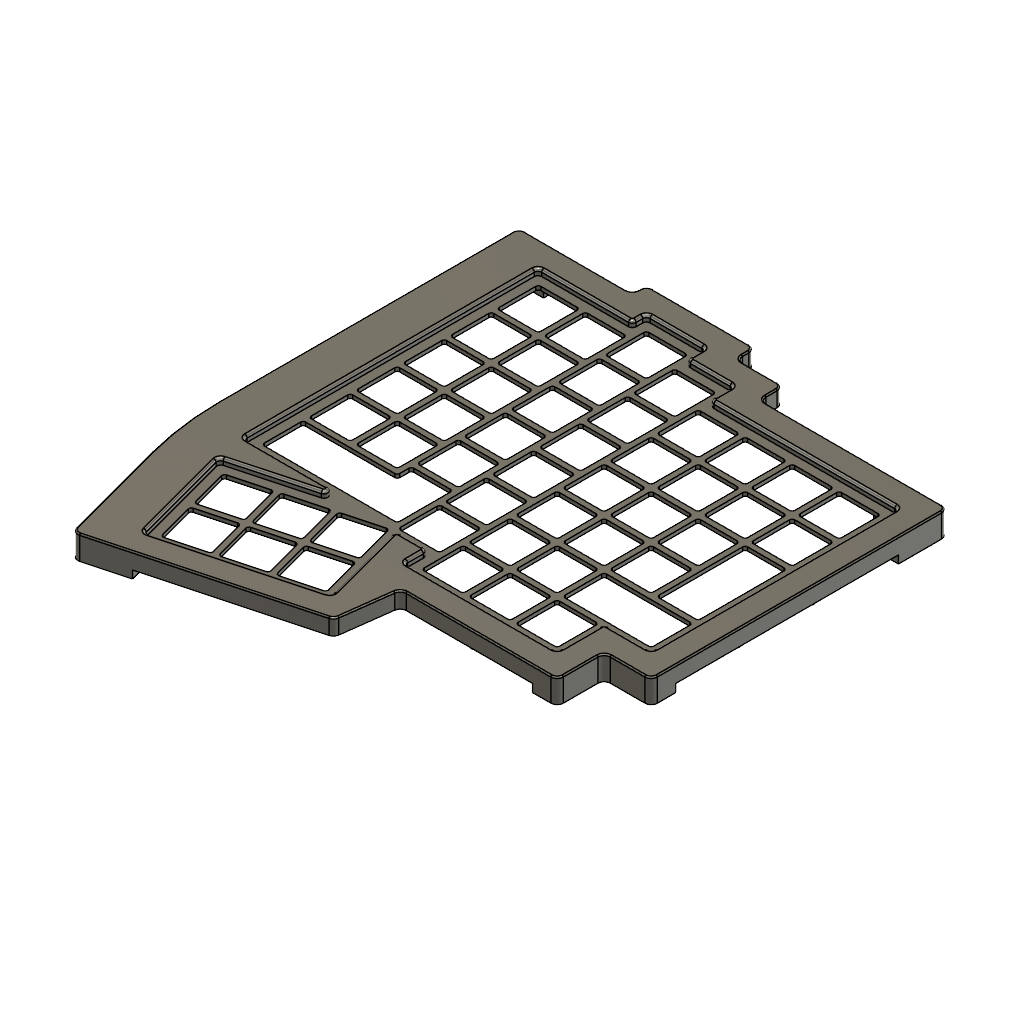
Assembly (Pollux) (Autodesk Fusion 360 archive; units mm, degrees)
design "Case Top (Pollux)" references "_Base (Pollux)"
part number: 2026-10-18-20-24-08-902
Autodesk Fusion 360 part; units mm, degrees
(part 1 of 6)
derive "ExternalDerived1"
sketch "Sketch2" plane through (0, 0, 0) normal (0, 1, 0) x (1, 0, 0)
  line L0 (-76.2, 57.15) -> (-76.2, -57.15) construction
  line L1 (76.2, -49.53) -> (76.2, 45.72) construction
  line L2 (-76.2, 57.15) -> (-38.1, 57.15) construction
  line L3 (-38.1, 57.15) -> (-38.1, 62.865) construction
  line L4 (-38.1, 62.865) -> (-19.05, 62.865) construction
  line L5 (-19.05, 62.865) -> (-19.05, 55.245) construction
  line L6 (-19.05, 55.245) -> (0, 55.245) construction
  line L7 (0, 55.245) -> (0, 45.72) construction
  line L8 (0, 45.72) -> (76.2, 45.72) construction
  line L9 (0, 45.72) -> (19.05, 45.72) construction
  line L10 (38.1, 45.72) -> (57.15, 45.72) construction
  line L11 (-76.2, 57.15) -> (-57.15, 57.15) construction
  line L12 (-57.15, 57.15) -> (-57.15, 38.1) construction
  line L13 (-57.15, 38.1) -> (-76.2, 38.1) construction
  line L14 (-38.1, 57.15) -> (-38.1, -38.1) construction
  line L15 (-38.1, -38.1) -> (-76.2, -38.1) construction
  line L16 (-57.15, 38.1) -> (-76.2, 57.15) construction
  line L17 (-76.2, 38.1) -> (-57.15, 57.15) construction
  line L18 (-19.05, 55.245) -> (-19.05, 43.815) construction
  line L19 (-19.05, 43.815) -> (-38.1, 43.815) construction
  line L20 (-19.05, 43.815) -> (-19.05, -32.385) construction
  line L21 (-19.05, -32.385) -> (-38.1, -32.385) construction
  line L22 (-38.1, 62.865) -> (-19.05, 43.815) construction
  line L23 (-38.1, 43.815) -> (-19.05, 62.865) construction
  line L24 (0, 45.72) -> (0, 36.195) construction
  line L25 (0, 36.195) -> (-19.05, 36.195) construction
  line L26 (0, 36.195) -> (0, -59.055) construction
  line L27 (0, -59.055) -> (-19.05, -59.055) construction
  line L28 (-19.05, -59.055) -> (-19.05, -32.385) construction
  line L29 (19.05, 45.72) -> (19.05, 26.67) construction
  line L30 (19.05, 26.67) -> (0, 26.67) construction
  line L31 (19.05, 26.67) -> (0, 45.72) construction
  line L32 (19.05, 45.72) -> (0, 26.67) construction
  line L33 (38.1, 45.72) -> (38.1, -68.58) construction
  line L34 (38.1, -68.58) -> (0, -68.58) construction
  line L35 (0, -68.58) -> (0, -59.055) construction
  line L36 (38.1, -68.58) -> (57.15, -68.58) construction
  line L37 (57.15, -68.58) -> (57.15, -49.53) construction
  line L38 (57.15, -49.53) -> (38.1, -49.53) construction
  line L39 (57.15, -49.53) -> (76.2, -49.53) construction
  line L40 (-76.2, -57.15) -> (-19.05, -57.15) construction
  line L41 (57.15, 45.72) -> (57.15, 26.67) construction
  line L42 (57.15, 26.67) -> (38.1, 26.67) construction
  line L43 (57.15, 26.67) -> (38.1, 45.72) construction
  line L44 (38.1, 26.67) -> (57.15, 45.72) construction
  line L45 (38.1, 26.67) -> (38.1, 7.62) construction
  line L46 (38.1, 7.62) -> (76.2, 7.62) construction
  line L47 (57.15, 7.62) -> (57.15, -30.48) construction
  line L48 (57.15, -30.48) -> (38.1, -30.48) construction
  line L49 (57.15, -11.43) -> (38.1, -11.43) construction
  line L50 (57.15, -30.48) -> (76.2, -30.48) construction
  line L51 (57.15, 7.62) -> (76.2, -30.48) construction
  line L52 (57.15, -30.48) -> (76.2, 7.62) construction
  line L53 (38.1, 7.62) -> (57.15, -11.43) construction
  line L54 (57.15, 7.62) -> (38.1, -11.43) construction
  line L55 (38.1, -30.48) -> (76.2, -49.53) construction
  line L56 (76.2, -30.48) -> (38.1, -49.53) construction
  line L57 (38.1, -49.53) -> (57.15, -68.58) construction
  line L58 (57.15, -49.53) -> (38.1, -68.58) construction
  line L59 (-76.2, -38.1) -> (-19.05, -57.15) construction
  line L60 (-38.1, -38.1) -> (-19.05, -38.1) construction
  line L61 (-19.05, -38.1) -> (-76.2, -57.15) construction
  line L62 (-76.2, 57.15) -> (-86.56, 57.15) construction
  line L63 (-86.56, 57.15) -> (-86.56, 59.625) construction
  line L64 (-38.1, 57.15) -> (-40.575, 57.15) construction
  line L65 (-40.575, 57.15) -> (-40.575, 59.625) construction
  line L66 (-38.1, 62.865) -> (-38.1, 65.34) construction
  line L67 (-38.1, 65.34) -> (-40.575, 65.34) construction
  line L68 (-19.05, 62.865) -> (-19.05, 65.34) construction
  line L69 (-19.05, 65.34) -> (-16.575, 65.34) construction
  line L70 (-19.05, 55.245) -> (-16.575, 55.245) construction
  line L71 (-16.575, 55.245) -> (-16.575, 57.72) construction
  line L72 (0, 55.245) -> (2.475, 55.245) construction
  line L73 (2.475, 55.245) -> (2.475, 57.72) construction
  line L74 (0, 45.72) -> (2.475, 45.72) construction
  line L75 (2.475, 45.72) -> (2.475, 48.195) construction
  line L76 (76.2, 45.72) -> (78.675, 45.72) construction
  line L77 (78.675, 45.72) -> (78.675, 48.195) construction
  line L78 (76.2, -49.53) -> (78.675, -49.53) construction
  line L79 (78.675, -49.53) -> (78.675, -52.005) construction
  line L80 (57.15, -49.53) -> (59.625, -49.53) construction
  line L81 (59.625, -49.53) -> (59.625, -52.005) construction
  line L82 (57.15, -68.58) -> (59.625, -68.58) construction
  line L83 (59.625, -68.58) -> (59.625, -71.055) construction
  line L84 (-19.05, -59.055) -> (-19.05, -59.16) construction
  line L85 (-19.05, -59.16) -> (-19.115, -59.16) construction
  line L86 (-19.115, -59.16) -> (-19.2509, -58.6529) construction
  line L87 (-19.2509, -58.6529) -> (-18.7438, -58.517) construction
  line L88 (-18.7438, -58.517) -> (-37.1447, -63.4475) construction
  line L89 (-37.1447, -63.4475) -> (-32.2142, -81.8484) construction
  line L90 (-32.2142, -81.8484) -> (-13.8133, -76.9179) construction
  line L91 (-13.8133, -76.9179) -> (-18.7438, -58.517) construction
  line L92 (-37.1447, -63.4475) -> (-73.9464, -73.3085) construction
  line L93 (-73.9464, -73.3085) -> (-64.0854, -110.1103) construction
  line L94 (-64.0854, -110.1103) -> (-8.8828, -95.3188) construction
  line L95 (-8.8828, -95.3188) -> (-13.8133, -76.9179) construction
  line L96 (-37.1447, -63.4475) -> (-13.8133, -76.9179) construction
  line L97 (-32.2142, -81.8484) -> (-18.7438, -58.517) construction
  line L98 (0, -68.58) -> (-2.475, -68.58) construction
  line L99 (-2.475, -68.58) -> (-2.475, -71.055) construction
  line L100 (-8.8828, -95.3188) -> (-6.4921, -94.6782) construction
  line L101 (-6.4921, -94.6782) -> (-5.8515, -97.0689) construction
  line L102 (-64.0854, -110.1103) -> (-74.0924, -112.7917) construction
  line L103 (-74.0924, -112.7917) -> (-73.4518, -115.1823) construction
  line L104 (-73.9464, -73.3085) -> (-83.9534, -75.9899) construction
  line L105 (-83.9534, -75.9899) -> (-84.594, -73.5992) construction
  line L106 (-76.2, -57.15) -> (-76.2, -59.625) construction
  line L107 (-76.2, -59.625) -> (-86.56, -59.625) construction
  line L108 (-84.594, -73.5992) -> (-73.4518, -115.1823)
  line L109 (-73.4518, -115.1823) -> (-5.8515, -97.0689)
  line L110 (-5.8515, -97.0689) -> (-2.475, -71.055)
  line L111 (-2.475, -71.055) -> (59.625, -71.055)
  line L112 (59.625, -71.055) -> (59.625, -52.005)
  line L113 (59.625, -52.005) -> (78.675, -52.005)
  line L114 (78.675, -52.005) -> (78.675, 48.195)
  line L115 (78.675, 48.195) -> (2.475, 48.195)
  line L116 (2.475, 48.195) -> (2.475, 57.72)
  line L117 (2.475, 57.72) -> (-16.575, 57.72)
  line L118 (-16.575, 57.72) -> (-16.575, 65.34)
  line L119 (-16.575, 65.34) -> (-40.575, 65.34)
  line L120 (-40.575, 65.34) -> (-40.575, 59.625)
  line L121 (-40.575, 59.625) -> (-86.56, 59.625)
  line L122 (-86.56, 59.625) -> (-86.56, -59.625)
  line L123 (-86.56, -59.625) -> (-84.594, -73.5992)
  line L124 (-19.5569, -59.9255) -> (-35.7362, -64.2607)
  line L125 (-35.7362, -64.2607) -> (-31.401, -80.4399)
  line L126 (-31.401, -80.4399) -> (-15.2217, -76.1047)
  line L127 (-15.2217, -76.1047) -> (-19.5569, -59.9255)
  line L128 (-19.5569, -59.9255) -> (-31.401, -80.4399) construction
  line L129 (-35.7362, -64.2607) -> (-15.2217, -76.1047) construction
  line L130 (-58.3, 56) -> (-75.05, 56)
  line L131 (-75.05, 56) -> (-75.05, 39.25)
  line L132 (-75.05, 39.25) -> (-58.3, 39.25)
  line L133 (-58.3, 39.25) -> (-58.3, 56)
  line L134 (-58.3, 56) -> (-75.05, 39.25) construction
  line L135 (-75.05, 56) -> (-58.3, 39.25) construction
  line L136 (-20.2, 61.715) -> (-36.95, 61.715)
  line L137 (-36.95, 61.715) -> (-36.95, 44.965)
  line L138 (-36.95, 44.965) -> (-20.2, 44.965)
  line L139 (-20.2, 44.965) -> (-20.2, 61.715)
  line L140 (-20.2, 61.715) -> (-36.95, 44.965) construction
  line L141 (-36.95, 61.715) -> (-20.2, 44.965) construction
  line L142 (-19.05, 55.245) -> (0, 36.195) construction
  line L143 (-19.05, 36.195) -> (0, 55.245) construction
  line L144 (-1.15, 54.095) -> (-17.9, 54.095)
  line L145 (-17.9, 54.095) -> (-17.9, 37.345)
  line L146 (-17.9, 37.345) -> (-1.15, 37.345)
  line L147 (-1.15, 37.345) -> (-1.15, 54.095)
  line L148 (-1.15, 54.095) -> (-17.9, 37.345) construction
  line L149 (-17.9, 54.095) -> (-1.15, 37.345) construction
  line L150 (17.9, 44.57) -> (1.15, 44.57)
  line L151 (1.15, 44.57) -> (1.15, 27.82)
  line L152 (1.15, 27.82) -> (17.9, 27.82)
  line L153 (17.9, 27.82) -> (17.9, 44.57)
  line L154 (17.9, 44.57) -> (1.15, 27.82) construction
  line L155 (1.15, 44.57) -> (17.9, 27.82) construction
  line L156 (56, 44.57) -> (39.25, 44.57)
  line L157 (39.25, 44.57) -> (39.25, 27.82)
  line L158 (39.25, 27.82) -> (56, 27.82)
  line L159 (56, 27.82) -> (56, 44.57)
  line L160 (56, 44.57) -> (39.25, 27.82) construction
  line L161 (39.25, 44.57) -> (56, 27.82) construction
  line L162 (56, 6.47) -> (39.25, 6.47)
  line L163 (39.25, 6.47) -> (39.25, -10.28)
  line L164 (39.25, -10.28) -> (56, -10.28)
  line L165 (56, -10.28) -> (56, 6.47)
  line L166 (56, 6.47) -> (39.25, -10.28) construction
  line L167 (39.25, 6.47) -> (56, -10.28) construction
  line L168 (75.05, 6.47) -> (58.3, 6.47)
  line L169 (58.3, 6.47) -> (58.3, -29.33)
  line L170 (58.3, -29.33) -> (75.05, -29.33)
  line L171 (75.05, -29.33) -> (75.05, 6.47)
  line L172 (75.05, 6.47) -> (58.3, -29.33) construction
  line L173 (58.3, 6.47) -> (75.05, -29.33) construction
  line L174 (75.05, -31.63) -> (39.25, -31.63)
  line L175 (39.25, -31.63) -> (39.25, -48.38)
  line L176 (39.25, -48.38) -> (75.05, -48.38)
  line L177 (75.05, -48.38) -> (75.05, -31.63)
  line L178 (75.05, -31.63) -> (39.25, -48.38) construction
  line L179 (39.25, -31.63) -> (75.05, -48.38) construction
  line L180 (56, -50.68) -> (39.25, -50.68)
  line L181 (39.25, -50.68) -> (39.25, -67.43)
  line L182 (39.25, -67.43) -> (56, -67.43)
  line L183 (56, -67.43) -> (56, -50.68)
  line L184 (56, -50.68) -> (39.25, -67.43) construction
  line L185 (39.25, -50.68) -> (56, -67.43) construction
  line L186 (-56, 56) -> (-56, 39.25)
  line L187 (-56, 39.25) -> (-39.25, 39.25)
  line L188 (-39.25, 39.25) -> (-39.25, 56)
  line L189 (-39.25, 56) -> (-56, 56)
  line L190 (-75.05, 36.95) -> (-75.05, 20.2)
  line L191 (-75.05, 20.2) -> (-58.3, 20.2)
  line L192 (-58.3, 20.2) -> (-58.3, 36.95)
  line L193 (-58.3, 36.95) -> (-75.05, 36.95)
  line L194 (-56, 36.95) -> (-56, 20.2)
  line L195 (-56, 20.2) -> (-39.25, 20.2)
  line L196 (-39.25, 20.2) -> (-39.25, 36.95)
  line L197 (-39.25, 36.95) -> (-56, 36.95)
  line L198 (-75.05, 17.9) -> (-75.05, 1.15)
  line L199 (-75.05, 1.15) -> (-58.3, 1.15)
  line L200 (-58.3, 1.15) -> (-58.3, 17.9)
  line L201 (-58.3, 17.9) -> (-75.05, 17.9)
  line L202 (-56, 17.9) -> (-56, 1.15)
  line L203 (-56, 1.15) -> (-39.25, 1.15)
  line L204 (-39.25, 1.15) -> (-39.25, 17.9)
  line L205 (-39.25, 17.9) -> (-56, 17.9)
  line L206 (-75.05, -1.15) -> (-75.05, -17.9)
  line L207 (-75.05, -17.9) -> (-58.3, -17.9)
  line L208 (-58.3, -17.9) -> (-58.3, -1.15)
  line L209 (-58.3, -1.15) -> (-75.05, -1.15)
  line L210 (-56, -1.15) -> (-56, -17.9)
  line L211 (-56, -17.9) -> (-39.25, -17.9)
  line L212 (-39.25, -17.9) -> (-39.25, -1.15)
  line L213 (-39.25, -1.15) -> (-56, -1.15)
  line L214 (-75.05, -20.2) -> (-75.05, -36.95)
  line L215 (-75.05, -36.95) -> (-58.3, -36.95)
  line L216 (-58.3, -36.95) -> (-58.3, -20.2)
  line L217 (-58.3, -20.2) -> (-75.05, -20.2)
  line L218 (-56, -20.2) -> (-56, -36.95)
  line L219 (-56, -36.95) -> (-39.25, -36.95)
  line L220 (-39.25, -36.95) -> (-39.25, -20.2)
  line L221 (-39.25, -20.2) -> (-56, -20.2)
  line L222 (-20.2, -39.25) -> (-75.05, -39.25)
  line L223 (-75.05, -39.25) -> (-75.05, -56)
  line L224 (-75.05, -56) -> (-20.2, -56)
  line L225 (-20.2, -56) -> (-20.2, -39.25)
  line L226 (-20.2, -39.25) -> (-75.05, -56) construction
  line L227 (-75.05, -39.25) -> (-20.2, -56) construction
  line L228 (-20.2, -39.25) -> (-36.95, -39.25)
  line L229 (-36.95, -39.25) -> (-36.95, -33.535)
  line L230 (-36.95, -33.535) -> (-20.2, -33.535)
  line L231 (-20.2, -33.535) -> (-20.2, -39.25)
  line L232 (-20.2, 42.665) -> (-36.95, 42.665)
  line L233 (-36.95, 42.665) -> (-36.95, 25.915)
  line L234 (-36.95, 25.915) -> (-20.2, 25.915)
  line L235 (-20.2, 25.915) -> (-20.2, 42.665)
  line L236 (-20.2, 23.615) -> (-36.95, 23.615)
  line L237 (-36.95, 23.615) -> (-36.95, 6.865)
  line L238 (-36.95, 6.865) -> (-20.2, 6.865)
  line L239 (-20.2, 6.865) -> (-20.2, 23.615)
  line L240 (-20.2, 4.565) -> (-36.95, 4.565)
  line L241 (-36.95, 4.565) -> (-36.95, -12.185)
  line L242 (-36.95, -12.185) -> (-20.2, -12.185)
  line L243 (-20.2, -12.185) -> (-20.2, 4.565)
  line L244 (-20.2, -14.485) -> (-36.95, -14.485)
  line L245 (-36.95, -14.485) -> (-36.95, -31.235)
  line L246 (-36.95, -31.235) -> (-20.2, -31.235)
  line L247 (-20.2, -31.235) -> (-20.2, -14.485)
  line L248 (-17.9, 35.045) -> (-17.9, 18.295)
  line L249 (-17.9, 18.295) -> (-1.15, 18.295)
  line L250 (-1.15, 18.295) -> (-1.15, 35.045)
  line L251 (-1.15, 35.045) -> (-17.9, 35.045)
  line L252 (-17.9, 15.995) -> (-17.9, -0.755)
  line L253 (-17.9, -0.755) -> (-1.15, -0.755)
  line L254 (-1.15, -0.755) -> (-1.15, 15.995)
  line L255 (-1.15, 15.995) -> (-17.9, 15.995)
  line L256 (-17.9, -3.055) -> (-17.9, -19.805)
  line L257 (-17.9, -19.805) -> (-1.15, -19.805)
  line L258 (-1.15, -19.805) -> (-1.15, -3.055)
  line L259 (-1.15, -3.055) -> (-17.9, -3.055)
  line L260 (-17.9, -22.105) -> (-17.9, -38.855)
  line L261 (-17.9, -38.855) -> (-1.15, -38.855)
  line L262 (-1.15, -38.855) -> (-1.15, -22.105)
  line L263 (-1.15, -22.105) -> (-17.9, -22.105)
  line L264 (-17.9, -41.155) -> (-17.9, -57.905)
  line L265 (-17.9, -57.905) -> (-1.15, -57.905)
  line L266 (-1.15, -57.905) -> (-1.15, -41.155)
  line L267 (-1.15, -41.155) -> (-17.9, -41.155)
  line L268 (20.2, 44.57) -> (20.2, 27.82)
  line L269 (20.2, 27.82) -> (36.95, 27.82)
  line L270 (36.95, 27.82) -> (36.95, 44.57)
  line L271 (36.95, 44.57) -> (20.2, 44.57)
  line L272 (1.15, 25.52) -> (1.15, 8.77)
  line L273 (1.15, 8.77) -> (17.9, 8.77)
  line L274 (17.9, 8.77) -> (17.9, 25.52)
  line L275 (17.9, 25.52) -> (1.15, 25.52)
  line L276 (20.2, 25.52) -> (20.2, 8.77)
  line L277 (20.2, 8.77) -> (36.95, 8.77)
  line L278 (36.95, 8.77) -> (36.95, 25.52)
  line L279 (36.95, 25.52) -> (20.2, 25.52)
  line L280 (1.15, 6.47) -> (1.15, -10.28)
  line L281 (1.15, -10.28) -> (17.9, -10.28)
  line L282 (17.9, -10.28) -> (17.9, 6.47)
  line L283 (17.9, 6.47) -> (1.15, 6.47)
  line L284 (20.2, 6.47) -> (20.2, -10.28)
  line L285 (20.2, -10.28) -> (36.95, -10.28)
  line L286 (36.95, -10.28) -> (36.95, 6.47)
  line L287 (36.95, 6.47) -> (20.2, 6.47)
  line L288 (1.15, -12.58) -> (1.15, -29.33)
  line L289 (1.15, -29.33) -> (17.9, -29.33)
  line L290 (17.9, -29.33) -> (17.9, -12.58)
  line L291 (17.9, -12.58) -> (1.15, -12.58)
  line L292 (20.2, -12.58) -> (20.2, -29.33)
  line L293 (20.2, -29.33) -> (36.95, -29.33)
  line L294 (36.95, -29.33) -> (36.95, -12.58)
  line L295 (36.95, -12.58) -> (20.2, -12.58)
  line L296 (1.15, -31.63) -> (1.15, -48.38)
  line L297 (1.15, -48.38) -> (17.9, -48.38)
  line L298 (17.9, -48.38) -> (17.9, -31.63)
  line L299 (17.9, -31.63) -> (1.15, -31.63)
  line L300 (20.2, -31.63) -> (20.2, -48.38)
  line L301 (20.2, -48.38) -> (36.95, -48.38)
  line L302 (36.95, -48.38) -> (36.95, -31.63)
  line L303 (36.95, -31.63) -> (20.2, -31.63)
  line L304 (1.15, -50.68) -> (1.15, -67.43)
  line L305 (1.15, -67.43) -> (17.9, -67.43)
  line L306 (17.9, -67.43) -> (17.9, -50.68)
  line L307 (17.9, -50.68) -> (1.15, -50.68)
  line L308 (20.2, -50.68) -> (20.2, -67.43)
  line L309 (20.2, -67.43) -> (36.95, -67.43)
  line L310 (36.95, -67.43) -> (36.95, -50.68)
  line L311 (36.95, -50.68) -> (20.2, -50.68)
  line L312 (58.3, 44.57) -> (58.3, 27.82)
  line L313 (58.3, 27.82) -> (75.05, 27.82)
  line L314 (75.05, 27.82) -> (75.05, 44.57)
  line L315 (75.05, 44.57) -> (58.3, 44.57)
  line L316 (39.25, 25.52) -> (39.25, 8.77)
  line L317 (39.25, 8.77) -> (56, 8.77)
  line L318 (56, 8.77) -> (56, 25.52)
  line L319 (56, 25.52) -> (39.25, 25.52)
  line L320 (58.3, 25.52) -> (58.3, 8.77)
  line L321 (58.3, 8.77) -> (75.05, 8.77)
  line L322 (75.05, 8.77) -> (75.05, 25.52)
  line L323 (75.05, 25.52) -> (58.3, 25.52)
  line L324 (56, -12.58) -> (39.25, -12.58)
  line L325 (39.25, -12.58) -> (39.25, -29.33)
  line L326 (39.25, -29.33) -> (56, -29.33)
  line L327 (56, -29.33) -> (56, -12.58)
  line L328 (-37.9578, -64.856) -> (-54.1371, -69.1912)
  line L329 (-54.1371, -69.1912) -> (-49.8019, -85.3704)
  line L330 (-49.8019, -85.3704) -> (-33.6226, -81.0352)
  line L331 (-33.6226, -81.0352) -> (-37.9578, -64.856)
  line L332 (-56.3587, -69.7865) -> (-72.538, -74.1217)
  line L333 (-72.538, -74.1217) -> (-68.2028, -90.3009)
  line L334 (-68.2028, -90.3009) -> (-52.0235, -85.9657)
  line L335 (-52.0235, -85.9657) -> (-56.3587, -69.7865)
  line L336 (-14.6264, -78.3264) -> (-30.8057, -82.6616)
  line L337 (-30.8057, -82.6616) -> (-26.4705, -98.8408)
  line L338 (-26.4705, -98.8408) -> (-10.2912, -94.5056)
  line L339 (-10.2912, -94.5056) -> (-14.6264, -78.3264)
  line L340 (-33.0273, -83.2569) -> (-49.2066, -87.5921)
  line L341 (-49.2066, -87.5921) -> (-44.8714, -103.7713)
  line L342 (-44.8714, -103.7713) -> (-28.6921, -99.4361)
  line L343 (-28.6921, -99.4361) -> (-33.0273, -83.2569)
  line L344 (-51.4282, -88.1874) -> (-67.6075, -92.5226)
  line L345 (-67.6075, -92.5226) -> (-63.2723, -108.7018)
  line L346 (-63.2723, -108.7018) -> (-47.093, -104.3666)
  line L347 (-47.093, -104.3666) -> (-51.4282, -88.1874)
  line L348 (-94.4114, -75.5973) -> (-80.5229, -127.4298)
  line L349 (-80.5229, -127.4298) -> (3.2035, -104.9953)
  line L350 (3.2035, -104.9953) -> (6.3109, -81.055)
  line L351 (6.3109, -81.055) -> (69.625, -81.055)
  line L352 (69.625, -81.055) -> (69.625, -62.005)
  line L353 (69.625, -62.005) -> (88.675, -62.005)
  line L354 (88.675, -62.005) -> (88.675, 58.195)
  line L355 (88.675, 58.195) -> (12.475, 58.195)
  line L356 (12.475, 58.195) -> (12.475, 67.72)
  line L357 (12.475, 67.72) -> (-6.575, 67.72)
  line L358 (-6.575, 67.72) -> (-6.575, 75.34)
  line L359 (-6.575, 75.34) -> (-50.575, 75.34)
  line L360 (-50.575, 75.34) -> (-50.575, 69.625)
  line L361 (-50.575, 69.625) -> (-96.56, 69.625)
  line L362 (-96.56, 69.625) -> (-96.56, -60.325)
  line L363 (-96.56, -60.325) -> (-94.4114, -75.5973)
  point P0 (-25.479, -70.1827)
  point P1 (-66.675, 47.625)
  point P2 (-28.575, 53.34)
  point P3 (-9.525, 45.72)
  point P4 (9.525, 36.195)
  point P5 (47.625, 36.195)
  point P6 (47.625, -1.905)
  point P7 (66.675, -11.43)
  point P8 (57.15, -40.005)
  point P9 (47.625, -59.055)
  point P10 (-47.625, -47.625)
  dimension "d67" = 114.3
  dimension "d68" = 38.1
  dimension "d69" = 5.715
  dimension "d70" = 19.05
  dimension "d71" = 7.62
  dimension "d72" = 19.05
  dimension "d73" = 9.525
  dimension "d74" = 19.05
  dimension "d75" = 19.05
  dimension "d76" = 19.05
  dimension "d77" = 95.25
  dimension "d78" = 11.43
  dimension "d79" = 76.2
  dimension "d80" = 9.525
  dimension "d81" = 95.25
  dimension "d82" = 19.05
  dimension "d83" = 19.05
  dimension "d84" = 114.3
  dimension "d85" = 38.1
  dimension "d86" = 19.05
  dimension "d87" = 19.05
  dimension "d88" = 19.05
  dimension "d89" = 19.05
  dimension "d90" = 38.1
  dimension "d91" = 10.36
  dimension "d92" = 2.475
  dimension "d93" = 2.475
  dimension "d94" = 2.475
  dimension "d95" = 2.475
  dimension "d96" = 2.475
  dimension "d97" = 2.475
  dimension "d98" = 2.475
  dimension "d99" = 2.475
  dimension "d100" = 2.475
  dimension "d101" = 2.475
  dimension "d102" = 2.475
  dimension "d103" = 2.475
  dimension "d104" = 2.475
  dimension "d105" = 2.475
  dimension "d106" = 2.475
  dimension "d107" = 2.475
  dimension "d108" = 2.475
  dimension "d109" = 2.475
  dimension "d110" = 2.475
  dimension "d111" = 2.475
  dimension "d112" = 2.475
  dimension "d113" = 0.105
  dimension "d114" = 0.065
  dimension "d115" = 0.525
  dimension "d116" = 0.525
  dimension "d117" = 19.05
  dimension "d118" = 19.05
  dimension "d119" = 38.1
  dimension "d120" = 38.1
  dimension "d121" = 57.15
  dimension "d122" = 2.475
  dimension "d123" = 2.475
  dimension "d124" = 2.475
  dimension "d125" = 2.475
  dimension "d126" = 10.36
  dimension "d127" = 2.475
  dimension "d128" = 10.36
  dimension "d129" = 2.475
  dimension "d130" = 2.475
  dimension "d131" = 10.36
  dimension "d132" = 16.75
  dimension "d133" = 16.75
  dimension "d134" = 16.75
  dimension "d135" = 16.75
  dimension "d136" = 16.75
  dimension "d137" = 16.75
  dimension "d138" = 16.75
  dimension "d139" = 16.75
  dimension "d140" = 16.75
  dimension "d141" = 16.75
  dimension "d142" = 16.75
  dimension "d143" = 16.75
  dimension "d144" = 16.75
  dimension "d145" = 16.75
  dimension "d146" = 16.75
  dimension "d147" = 35.8
  dimension "d148" = 35.8
  dimension "d149" = 16.75
  dimension "d150" = 16.75
  dimension "d151" = 16.75
  dimension "d154" = 19.05
  dimension "d156" = 54.85
  dimension "d157" = 16.75
  dimension "d158" = 16.75
  dimension "d159" = 5.715
  dimension "d162" = 0
  dimension "d166" = 0
  dimension "d170" = 19.05
  dimension "d174" = 19.05
  dimension "d178" = 0
  dimension "d182" = 19.05
  dimension "d183" = 19.05
  dimension "d184" = 10
  constraint parallel L0 L1
  constraint perpendicular L2 L3
  constraint perpendicular L0 L4
  constraint perpendicular L4 L5
  constraint perpendicular L5 L6
  constraint perpendicular L6 L7
  constraint perpendicular L1 L8
  constraint coincident L8 L9.end
  constraint midpoint L8 L10.start
  constraint coincident L8 L10.end
  constraint midpoint L2 L11.end
  constraint perpendicular L0 L11
  constraint perpendicular L2 L12
  constraint coincident L0 L13.end
  constraint perpendicular L0 L13
  constraint perpendicular L2 L14
  constraint coincident L0 L15.end
  constraint perpendicular L0 L15
  constraint perpendicular L6 L18
  constraint coincident L14 L19.end
  constraint perpendicular L14 L19
  constraint perpendicular L19 L20
  constraint coincident L14 L21.end
  constraint perpendicular L14 L21
  constraint perpendicular L8 L24
  constraint coincident L20 L25.end
  constraint perpendicular L20 L25
  constraint perpendicular L25 L26
  constraint perpendicular L26 L27
  constraint perpendicular L9 L29
  constraint coincident L26 L30.end
  constraint perpendicular L26 L30
  constraint perpendicular L10 L33
  constraint perpendicular L33 L34
  constraint perpendicular L27 L35
  constraint perpendicular L33 L36
  constraint coincident L33 L38.end
  constraint perpendicular L33 L38
  constraint perpendicular L1 L39
  constraint coincident L28 L40.end
  constraint perpendicular L10 L41
  constraint coincident L33 L42.end
  constraint perpendicular L33 L42
  constraint coincident L33 L45.end
  constraint coincident L1 L46.end
  constraint perpendicular L1 L46
  constraint midpoint L46 L47.start
  constraint perpendicular L46 L47
  constraint coincident L33 L48.end
  constraint perpendicular L33 L48
  constraint midpoint L47 L49.start
  constraint midpoint L33 L49.end
  constraint coincident L1 L50.end
  constraint perpendicular L1 L50
  constraint perpendicular L51 L56
  constraint perpendicular L57 L58
  constraint coincident L28 L60.end
  constraint perpendicular L28 L60
  constraint perpendicular L0 L62
  constraint perpendicular L62 L63
  constraint coincident L2 L64.end
  constraint perpendicular L64 L65
  constraint perpendicular L4 L66
  constraint perpendicular L3 L67
  constraint perpendicular L4 L68
  constraint perpendicular L5 L69
  constraint coincident L6 L70.end
  constraint perpendicular L70 L71
  constraint perpendicular L7 L72
  constraint perpendicular L72 L73
  constraint coincident L9 L74.end
  constraint perpendicular L74 L75
  constraint perpendicular L1 L76
  constraint perpendicular L8 L77
  constraint perpendicular L1 L78
  constraint perpendicular L39 L79
  constraint coincident L39 L80.end
  constraint perpendicular L39 L81
  constraint perpendicular L37 L82
  constraint perpendicular L36 L83
  constraint perpendicular L27 L84
  constraint perpendicular L86 L87
  constraint perpendicular L84 L85
  constraint collinear L87 L88
  constraint parallel L89 L91
  constraint parallel L88 L90
  constraint perpendicular L89 L90
  constraint perpendicular L89 L92
  constraint perpendicular L88 L93
  constraint perpendicular L89 L94
  constraint perpendicular L35 L98
  constraint perpendicular L34 L99
  constraint perpendicular L95 L100
  constraint perpendicular L100 L101
  constraint perpendicular L93 L102
  constraint perpendicular L102 L103
  constraint perpendicular L93 L104
  constraint perpendicular L104 L105
  constraint perpendicular L40 L106
  constraint perpendicular L0 L107
  constraint perpendicular L107 L122
  constraint perpendicular L124 L125
  constraint parallel L124 L126
  constraint parallel L125 L127
  constraint coincident L128 P0
  constraint coincident L129 P0
  constraint midpoint L96 P0
  constraint horizontal L130
  constraint perpendicular L130 L131
  constraint parallel L130 L132
  constraint parallel L131 L133
  constraint coincident L134 P1
  constraint coincident L135 P1
  constraint midpoint L16 P1
  constraint horizontal L136
  constraint perpendicular L136 L137
  constraint parallel L136 L138
  constraint parallel L137 L139
  constraint coincident L140 P2
  constraint coincident L141 P2
  constraint midpoint L22 P2
  constraint horizontal L144
  constraint perpendicular L144 L145
  constraint parallel L144 L146
  constraint parallel L145 L147
  constraint coincident L148 P3
  constraint coincident L149 P3
  constraint midpoint L142 P3
  constraint horizontal L150
  constraint perpendicular L150 L151
  constraint parallel L150 L152
  constraint parallel L151 L153
  constraint coincident L154 P4
  constraint coincident L155 P4
  constraint midpoint L31 P4
  constraint horizontal L156
  constraint perpendicular L156 L157
  constraint parallel L156 L158
  constraint parallel L157 L159
  constraint coincident L160 P5
  constraint coincident L161 P5
  constraint midpoint L43 P5
  constraint horizontal L162
  constraint perpendicular L162 L163
  constraint parallel L162 L164
  constraint parallel L163 L165
  constraint coincident L166 P6
  constraint coincident L167 P6
  constraint midpoint L54 P6
  constraint horizontal L168
  constraint perpendicular L168 L169
  constraint parallel L168 L170
  constraint parallel L169 L171
  constraint coincident L172 P7
  constraint coincident L173 P7
  constraint midpoint L51 P7
  constraint horizontal L174
  constraint perpendicular L174 L175
  constraint parallel L174 L176
  constraint parallel L175 L177
  constraint coincident L178 P8
  constraint coincident L179 P8
  constraint midpoint L55 P8
  constraint horizontal L180
  constraint perpendicular L180 L181
  constraint parallel L180 L182
  constraint parallel L181 L183
  constraint coincident L184 P9
  constraint coincident L185 P9
  constraint midpoint L58 P9
  constraint horizontal L222
  constraint perpendicular L222 L223
  constraint parallel L222 L224
  constraint parallel L223 L225
  constraint coincident L226 P10
  constraint coincident L227 P10
  constraint midpoint L61 P10
  constraint horizontal L228
  constraint vertical L229
  constraint horizontal L230
  constraint vertical L231
  measures "d67" distance of L0.start L0.end
  measures "d68" distance of L0.start L2.end
  measures "d69" distance of L2.end L3.end
  measures "d70" distance of L3.end L4.end
  measures "d71" distance of L4.end L5.end
  measures "d72" distance of L5.end L6.end
  measures "d73" distance of L6.end L7.end
  measures "d74" distance of L7.end L9.end
  measures "d75" distance of L10.start L10.end
  measures "d76" distance of L11.end L12.end
  measures "d77" distance of L2.end L14.end
  measures "d78" distance of L5.end L18.end
  measures "d79" distance of L18.end L20.end
  measures "d80" distance of L7.end L24.end
  measures "d81" distance of L24.end L26.end
  measures "d82" distance of L26.end L27.end
  measures "d83" distance of L9.end L29.end
  measures "d84" distance of L10.start L33.end
  measures "d85" distance of L33.end L34.end
  measures "d86" distance of L33.end L36.end
  measures "d87" distance of L36.end L37.end
  measures "d88" distance of L10.end L41.end
  measures "d89" distance of L42.end L45.end
  measures "d90" distance of L47.start L47.end
  measures "d91" distance of L0.start L62.end
  measures "d92" distance of L62.end L63.end
  measures "d93" distance of L2.end L64.end
  measures "d94" distance of L64.end L65.end
  measures "d95" distance of L3.end L66.end
  measures "d96" distance of L66.end L67.end
  measures "d97" distance of L4.end L68.end
  measures "d98" distance of L68.end L69.end
  measures "d99" distance of L5.end L70.end
  measures "d100" distance of L70.end L71.end
  measures "d101" distance of L6.end L72.end
  measures "d102" distance of L72.end L73.end
  measures "d103" distance of L7.end L74.end
  measures "d104" distance of L74.end L75.end
  measures "d105" distance of L1.end L76.end
  measures "d106" distance of L76.end L77.end
  measures "d107" distance of L1.start L78.end
  measures "d108" distance of L78.end L79.end
  measures "d109" distance of L37.end L80.end
  measures "d110" distance of L80.end L81.end
  measures "d111" distance of L36.end L82.end
  measures "d112" distance of L82.end L83.end
  measures "d113" distance of L27.end L84.end
  measures "d114" distance of L84.end L85.end
  measures "d115" distance of L85.end L86.end
  measures "d116" distance of L86.end L87.end
  measures "d117" distance of L87.end L88.end
  measures "d118" distance of L87.end L90.end
  measures "d119" distance of L88.end L92.end
  measures "d120" distance of L92.end L93.end
  measures "d121" distance of L93.end L94.end
  measures "d122" distance of L34.end L98.end
  measures "d123" distance of L98.end L99.end
  measures "d124" distance of L94.end L100.end
  measures "d125" distance of L100.end L101.end
  measures "d126" distance of L93.end L102.end
  measures "d127" distance of L102.end L103.end
  measures "d128" distance of L92.end L104.end
  measures "d129" distance of L104.end L105.end
  measures "d130" distance of L0.end L106.end
  measures "d131" distance of L106.end L107.end
  measures "d132" distance of L125.end L126.end
  measures "d133" distance of L124.end L125.end
  measures "d134" distance of L131.end L132.end
  measures "d135" distance of L130.end L131.end
  measures "d136" distance of L137.end L138.end
  measures "d137" distance of L136.end L137.end
  measures "d138" distance of L145.end L146.end
  measures "d139" distance of L144.end L145.end
  measures "d140" distance of L151.end L152.end
  measures "d141" distance of L150.end L151.end
  measures "d142" distance of L157.end L158.end
  measures "d143" distance of L156.end L157.end
  measures "d144" distance of L163.end L164.end
  measures "d145" distance of L162.end L163.end
  measures "d146" distance of L169.end L170.end
  measures "d147" distance of L168.end L169.end
  measures "d148" distance of L175.end L176.end
  measures "d149" distance of L174.end L175.end
  measures "d150" distance of L181.end L182.end
  measures "d151" distance of L180.end L181.end
  measures "d156" distance of L223.end L224.end
  measures "d157" distance of L222.end L223.end
  measures "d158" distance of L222.start L228.end
  measures "d159" distance of L222.start L230.end
extrude "Extrude1" add sketch "Sketch2" against normal blind 1.5 contours L108 L109 L110 L111 L112 L113 L114 L115 L116 L117 L118 L119 L120 L121 L122 L123
extrude "Extrude2" add sketch "Sketch2" against normal blind 4 contours L348 L349 L350 L351 L352 L353 L354 L355 L356 L357 L358 L359 L360 L361 L362 L363
sketch "Sketch3" plane through (0, -4, 0) normal (0, -1, 0) x (1, 0, 0)
  line L0 (-86.56, 59.625) -> (-84.594, 73.5992)
  line L1 (-84.594, 73.5992) -> (-73.4518, 115.1823)
  line L2 (-73.4518, 115.1823) -> (-5.8515, 97.0689)
  line L3 (-5.8515, 97.0689) -> (-2.475, 71.055)
  line L4 (-2.475, 71.055) -> (59.625, 71.055)
  line L5 (59.625, 71.055) -> (59.625, 52.005)
  line L6 (59.625, 52.005) -> (78.675, 52.005)
  line L7 (78.675, 52.005) -> (78.675, -48.195)
  line L8 (78.675, -48.195) -> (2.475, -48.195)
  line L9 (2.475, -48.195) -> (2.475, -57.72)
  line L10 (2.475, -57.72) -> (-16.575, -57.72)
  line L11 (-16.575, -57.72) -> (-16.575, -65.34)
  line L12 (-16.575, -65.34) -> (-40.575, -65.34)
  line L13 (-40.575, -65.34) -> (-40.575, -59.625)
  line L14 (-40.575, -59.625) -> (-86.56, -59.625)
  line L15 (-86.56, -59.625) -> (-86.56, 59.625)
  line L16 (-94.4114, 75.5973) -> (-96.56, 60.325)
  line L17 (-96.56, 60.325) -> (-96.56, -69.625)
  line L18 (-96.56, -69.625) -> (-50.575, -69.625)
  line L19 (-50.575, -69.625) -> (-50.575, -75.34)
  line L20 (-50.575, -75.34) -> (-6.575, -75.34)
  line L21 (-6.575, -75.34) -> (-6.575, -67.72)
  line L22 (-6.575, -67.72) -> (12.475, -67.72)
  line L23 (12.475, -67.72) -> (12.475, -58.195)
  line L24 (12.475, -58.195) -> (88.675, -58.195)
  line L25 (88.675, -58.195) -> (88.675, 62.005)
  line L26 (88.675, 62.005) -> (69.625, 62.005)
  line L27 (69.625, 62.005) -> (69.625, 81.055)
  line L28 (69.625, 81.055) -> (6.3109, 81.055)
  line L29 (6.3109, 81.055) -> (3.2035, 104.9953)
  line L30 (3.2035, 104.9953) -> (-80.5229, 127.4298)
  line L31 (-80.5229, 127.4298) -> (-94.4114, 75.5973)
  line L32 (78.675, -48.195) -> (68.675, -48.195) construction
  line L33 (68.675, -48.195) -> (68.675, -58.195)
  line L34 (78.675, -48.195) -> (78.675, -38.195) construction
  line L35 (78.675, -38.195) -> (88.675, -38.195)
  line L36 (78.675, 52.005) -> (88.675, 52.005)
  line L37 (59.625, 71.055) -> (59.625, 81.055)
  line L38 (-73.4518, 115.1823) -> (-76.04, 105.5231) construction
  line L39 (-73.4518, 115.1823) -> (-63.7926, 112.5941) construction
  line L40 (-63.7926, 112.5941) -> (-61.2044, 122.2534)
  line L41 (-76.04, 105.5231) -> (-85.6993, 108.1113)
  line L42 (-86.56, -59.625) -> (-76.56, -59.625) construction
  line L43 (-86.56, -59.625) -> (-86.56, -49.625) construction
  line L44 (-86.56, -49.625) -> (-96.56, -49.625)
  line L45 (-76.56, -59.625) -> (-76.56, -69.625)
  dimension "d189" = 10
  dimension "d190" = 10
  dimension "d191" = 10
  dimension "d192" = 10
  dimension "d193" = 10
  dimension "d194" = 10
  constraint coincident L7.end L8.start
  constraint coincident L8 L32.end
  constraint coincident L24 L33.end
  constraint perpendicular L24 L33
  constraint perpendicular L8 L34
  constraint coincident L25 L35.end
  constraint perpendicular L25 L35
  constraint coincident L6.end L7.start
  constraint coincident L25 L36.end
  constraint perpendicular L25 L36
  constraint coincident L4.end L5.start
  constraint coincident L28 L37.end
  constraint perpendicular L28 L37
  constraint coincident L1.end L2.start
  constraint coincident L1 L38.end
  constraint coincident L2 L39.end
  constraint coincident L30 L40.end
  constraint perpendicular L30 L40
  constraint coincident L31 L41.end
  constraint perpendicular L31 L41
  constraint coincident L14.end L15.start
  constraint coincident L14 L42.end
  constraint coincident L15 L43.end
  constraint coincident L17 L44.end
  constraint perpendicular L17 L44
  constraint coincident L18 L45.end
  constraint perpendicular L18 L45
  measures "d189" distance of L7.end L32.end
  measures "d190" distance of L7.end L34.end
  measures "d191" distance of L1.end L38.end
  measures "d192" distance of L1.end L39.end
  measures "d193" distance of L14.end L42.end
  measures "d194" distance of L14.end L43.end
extrude "Extrude3" add sketch "Sketch3" along normal blind 3.2 contours L14 L15 L17 L18 L44 L45 | L1 L2 L30 L31 L40 L41 | L5 L6 L25 L26 L27 L28 L36 L37 | L7 L8 L24 L25 L33 L35
sketch "Sketch4" plane through (0, -7.2, 0) normal (0, -1, 0) x (1, 0, 0)
  line L0 (78.675, -48.195) -> (68.675, -48.195)
  line L1 (68.675, -48.195) -> (68.675, -58.195)
  line L2 (68.675, -58.195) -> (88.675, -58.195)
  line L3 (88.675, -58.195) -> (88.675, -38.195)
  line L4 (88.675, -38.195) -> (78.675, -38.195)
  line L5 (78.675, -38.195) -> (78.675, -48.195)
  line L6 (88.675, -58.195) -> (78.675, -48.195) construction
  circle A0 centre (88.675, -58.195) radius 8.75 construction
  circle A1 centre (82.4878, -52.0078) radius 1.75
  dimension "d197" = 17.5
  dimension "d198" = 3.5
  constraint coincident L2.end L3.start
  constraint coincident L0.start L5.end
  constraint coincident A0 A1.centre
  constraint coincident L6 A1.centre
  measures "d197" diameter of A0
  measures "d198" diameter of A1
sketch "Sketch5" plane through (0, -7.2, 0) normal (0, -1, 0) x (1, 0, 0)
  line L0 (59.625, 52.005) -> (88.675, 52.005)
  line L1 (88.675, 52.005) -> (88.675, 62.005)
  line L2 (88.675, 62.005) -> (69.625, 62.005)
  line L3 (69.625, 62.005) -> (69.625, 81.055)
  line L4 (69.625, 81.055) -> (59.625, 81.055)
  line L5 (59.625, 81.055) -> (59.625, 52.005)
  line L6 (69.625, 62.005) -> (59.625, 52.005) construction
  circle A0 centre (69.625, 62.005) radius 6.25 construction
  circle A1 centre (65.2056, 57.5856) radius 1.75
  dimension "d199" = 12.5
  dimension "d200" = 3.5
  constraint coincident L2.end L3.start
  constraint coincident L0.start L5.end
  constraint coincident A0 A1.centre
  constraint coincident L6 A1.centre
  measures "d199" diameter of A0
  measures "d200" diameter of A1
sketch "Sketch6" plane through (0, -7.2, 0) normal (0, -1, 0) x (1, 0, 0)
  line L0 (-73.4518, 115.1823) -> (-63.7926, 112.5941)
  line L1 (-63.7926, 112.5941) -> (-61.2044, 122.2534)
  line L2 (-61.2044, 122.2534) -> (-80.5229, 127.4298)
  line L3 (-80.5229, 127.4298) -> (-85.6993, 108.1113)
  line L4 (-85.6993, 108.1113) -> (-76.04, 105.5231)
  line L5 (-76.04, 105.5231) -> (-73.4518, 115.1823)
  line L6 (-73.4518, 115.1823) -> (-80.5229, 127.4298) construction
  circle A0 centre (-80.5229, 127.4298) radius 8.75 construction
  circle A1 centre (-76.1479, 119.852) radius 1.75
  dimension "d201" = 17.5
  dimension "d202" = 3.5
  constraint coincident L0.start L5.end
  constraint coincident L2.end L3.start
  constraint coincident A0 A1.centre
  constraint coincident L6 A1.centre
  measures "d201" diameter of A0
  measures "d202" diameter of A1
sketch "Sketch7" plane through (0, -7.2, 0) normal (0, -1, 0) x (1, 0, 0)
  line L0 (-86.56, -59.625) -> (-86.56, -49.625)
  line L1 (-86.56, -49.625) -> (-96.56, -49.625)
  line L2 (-96.56, -49.625) -> (-96.56, -69.625)
  line L3 (-96.56, -69.625) -> (-76.56, -69.625)
  line L4 (-76.56, -69.625) -> (-76.56, -59.625)
  line L5 (-76.56, -59.625) -> (-86.56, -59.625)
  line L6 (-86.56, -59.625) -> (-96.56, -69.625) construction
  circle A0 centre (-96.56, -69.625) radius 8.75 construction
  circle A1 centre (-90.3728, -63.4378) radius 1.75
  dimension "d203" = 17.5
  dimension "d204" = 3.5
  constraint coincident L0.start L5.end
  constraint coincident L2.end L3.start
  constraint coincident A0 A1.centre
  constraint coincident L6 A1.centre
  measures "d203" diameter of A0
  measures "d204" diameter of A1
extrude "Extrude4" cut sketch "Sketch4" sketch "Sketch5" sketch "Sketch6" sketch "Sketch7" against normal blind 2.5 contours A1 of sketch 2 contours A1 of sketch 3 contours A1 of sketch 4 contours A1